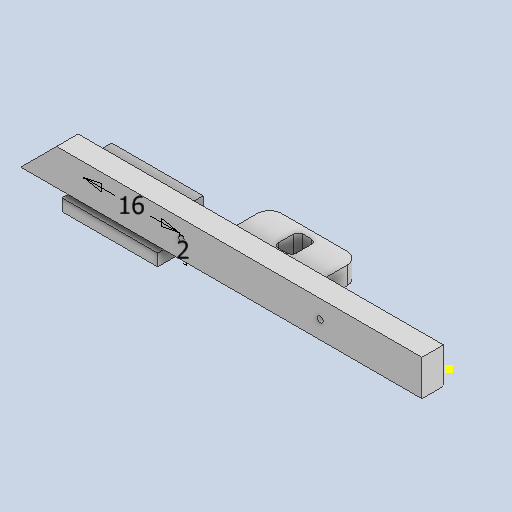
# Autodesk Inventor part: micro_switch_cap
Saved by Autodesk Inventor 2025 (Build 290162000, 162)
## iProperties
Created: 2026-11-09
Part Number: micro_switch_cap
Material: Типовые
Document SubType Name: Modeling
Designer: garin
Density: 1 g/cm^3
Appearance: По умолчанию
Author: garin
Autodesk Inventor part; units mm, degrees
ref_plane "YZ Plane" through (0, 0, 0) normal (1, 0, 0) x (0, 1, 0)
ref_plane "XZ Plane" through (0, 0, 0) normal (0, 1, 0) x (-1, 0, 0)
ref_plane "XY Plane" through (0, 0, 0) normal (0, 0, 1) x (1, 0, 0)
sketch "Эскиз1" plane through (0, 0, 0) normal (0, 0, 1) x (1, 0, 0)
  line L0 (0, 0) -> (-1, 0) construction
  line L1 (-68.1, 3) -> (-1, 3)
  line L2 (-1, 3) -> (-1, -3)
  line L3 (-1, -3) -> (-68.1, -3)
  line L4 (-68.1, -3) -> (-68.1, 3)
  line L5 (-68.1, -3) -> (-62.1, 3)
  line L6 (-68.1, -3) -> (-59.6147, -3) construction
  dimension "d0" = 1
  dimension "d1" = 6
  dimension "d2" = 67.1
  dimension "d3" = 45
  constraints: 14 end point, 3 horizontal, 2 parallel, 1 equal length, 1 midpoint, 1 perpendicular, 1 point on line
  measures "d0" distance of L0.end L0.start
  measures "d1" distance of L1.end L2.end
  measures "d2" distance of L2.end L3.end
  measures "d3" angle of L6 L5
extrude "Выдавливание1" add sketch "Эскиз1" along normal blind 3.6 contours L1 L2 L3 L5
sketch "Эскиз2" plane through (0, 0, 0) normal (0, 0, -1) x (-1, 0, 0)
  line L0 (44.7, 1) -> (60.7, 1) projected
  line L1 (60.7, 1) -> (61.7, 0) projected
  line L2 (61.7, 0) -> (61.7, -3.5) projected
  line L3 (44.7, 1) -> (44.7, -4) projected
  line L4 (44.7, -4) -> (44.7, -6)
  line L5 (44.7, -6) -> (61.7, -6)
  line L6 (61.7, -6) -> (61.7, -3.5)
  line L7 (60.4929, 0.5) -> (45.2, 0.5)
  line L8 (45.2, 0.5) -> (45.2, -4)
  line L9 (45.2, -4) -> (45.2, -5.5)
  line L10 (45.2, -5.5) -> (61.2, -5.5)
  line L11 (61.2, -5.5) -> (61.2, -3.5)
  line L12 (61.2, -3.5) -> (61.2, -0.2071)
  line L13 (61.2, -0.2071) -> (60.4929, 0.5)
  line L14 (61.2, -5.5) -> (61.2, -6)
  line L15 (45.2, -5.5) -> (45.2, -6)
  point P0 (0, 0)
  dimension "d6" = 2
  dimension "d7" = 0.5
  constraints: 24 end point, 6 perpendicular, 2 point on line, 1 vertical, 6 other
  measures "d6" distance of L3.end L4.end
  measures "d7" distance between parallel lines of L0 L7
extrude "Выдавливание2" add sketch "Эскиз2" along normal blind 4 contours L15 L10 L14 L5 | L9 L8 L7 L13 L12 L11 L10
sketch "Эскиз3" plane through (0, 0, 0) normal (0, 0, 1) x (1, 0, 0)
  line L0 (-61.2, -6) -> (-61.2, -3) projected
  line L1 (-68.1, -3) -> (-1, -3) projected
  line L2 (-61.2, -6) -> (-45.2, -6)
  line L3 (-45.2, -6) -> (-45.2, -3)
  line L4 (-45.2, -3) -> (-61.2, -3)
  line L5 (-61.2, -3) -> (-61.2, -6)
  line L6 (-61.2, -6) -> (-45.2, -6)
  line L7 (-45.2, -6) -> (-45.2, -4)
  line L8 (-45.2, -4) -> (-61.2, -4)
  line L9 (-61.2, -4) -> (-61.2, -6)
  point P0 (0, 0)
  dimension "d10" = 16
  dimension "d11" = 2
  constraints: 16 end point, 4 parallel, 2 horizontal, 2 perpendicular, 2 point on line
  measures "d10" distance of L4.end L3.end
  measures "d11" distance of L7.end L6.end
extrude "Выдавливание3" add sketch "Эскиз3" along normal blind 3.6
extrude "Выдавливание4" cut sketch "Эскиз3" against normal blind 1 from surface at 3.6 contours L0 L1 L3 L8
sketch "Эскиз4" plane through (0, 0, 0) normal (0, 0, -1) x (-1, 0, 0)
  circle A0 centre (41.2, 0) radius 0.5 projected
  circle A1 centre (41.2, 0) radius 2.5 projected
  line L0 (37.6, 1.5) -> (21.6, 1.5) projected
  line L1 (37.6, -1.5) -> (37.6, 1.5) projected
  line L2 (21.6, -1.5) -> (37.6, -1.5) projected
  line L3 (21.6, 1.5) -> (21.6, -1.5) projected
  circle A2 centre (18, 0) radius 0.5 projected
  circle A3 centre (18, 0) radius 2.5 projected
  line L4 (21.75, 1.35) -> (37.45, 1.35)
  line L5 (37.45, 1.35) -> (37.45, -1.35)
  line L6 (37.45, -1.35) -> (21.75, -1.35)
  line L7 (21.75, -1.35) -> (21.75, 1.35)
  point P0 (0, 0)
  dimension "d16" = 0.15
  constraints: 8 end point, 3 other
  measures "d16" distance between parallel lines of L0 L4
extrude "Выдавливание5" cut sketch "Эскиз4" against normal blind 2 contours A0 | A1 | A2 | A3
sketch "Эскиз5" plane through (0, 0, 0) normal (0, 0, -1) x (-1, 0, 0)
  circle A0 centre (41.2, 0) radius 0.5 projected
  circle A1 centre (18, 0) radius 0.5 projected
  line L0 (-44.7, 1) -> (-60.7, 1) projected
  line L1 (-61.7, 0) -> (-60.7, 1) projected
  line L2 (-61.7, -3.5) -> (-61.7, 0) projected
  line L3 (-61.7, -3.5) -> (-68.2, -3.5) projected
  line L4 (-68.2, -3) -> (-68.2, -3.5) projected
  line L5 (-61.2, 4) -> (-68.2, -3) projected
  line L6 (-61.2, 4) -> (61.2, 4) projected
  line L7 (68.2, -3) -> (61.2, 4) projected
  line L8 (68.2, -3.5) -> (68.2, -3) projected
  line L9 (68.2, -3.5) -> (61.7, -3.5) projected
  line L10 (61.7, 0) -> (61.7, -3.5) projected
  line L11 (60.7, 1) -> (61.7, 0) projected
  line L12 (44.7, 1) -> (60.7, 1) projected
  line L13 (44.7, 1) -> (44.7, -4) projected
  line L14 (44.7, -4) -> (-44.7, -4) projected
  line L15 (-44.7, -4) -> (-44.7, 1) projected
  circle A2 centre (41.2, 0) radius 2.5 projected
  circle A3 centre (18, 0) radius 2.5 projected
  line L16 (21.6, 1.5) -> (21.6, -1.5) projected
  line L17 (21.6, -1.5) -> (37.6, -1.5) projected
  line L18 (37.6, -1.5) -> (37.6, 1.5) projected
  line L19 (37.6, 1.5) -> (21.6, 1.5) projected
  circle A4 centre (-41.2, 0) radius 2.5 projected
  circle A5 centre (-18, 0) radius 2.5 projected
  line L20 (-21.6, -1.5) -> (-21.6, 1.5) projected
  line L21 (-21.6, 1.5) -> (-37.6, 1.5) projected
  line L22 (-37.6, 1.5) -> (-37.6, -1.5) projected
  line L23 (-37.6, -1.5) -> (-21.6, -1.5) projected
  point P0 (0, 0)
extrude "Выдавливание6" cut sketch "Эскиз5" against normal blind 3.6 contours A0 | A1
sketch "Эскиз6" plane through (0, 0, 0) normal (0, 0, -1) x (-1, 0, 0)
  line L0 (-44.7, 1) -> (-60.7, 1) projected
  line L1 (-61.7, 0) -> (-60.7, 1) projected
  line L2 (-61.7, -3.5) -> (-61.7, 0) projected
  line L3 (-61.7, -3.5) -> (-68.2, -3.5) projected
  line L4 (-68.2, -3) -> (-68.2, -3.5) projected
  line L5 (-61.2, 4) -> (-68.2, -3) projected
  line L6 (-61.2, 4) -> (61.2, 4) projected
  line L7 (68.2, -3) -> (61.2, 4) projected
  line L8 (68.2, -3.5) -> (68.2, -3) projected
  line L9 (68.2, -3.5) -> (61.7, -3.5) projected
  line L10 (61.7, 0) -> (61.7, -3.5) projected
  line L11 (60.7, 1) -> (61.7, 0) projected
  line L12 (44.7, 1) -> (60.7, 1) projected
  line L13 (44.7, 1) -> (44.7, -4) projected
  line L14 (44.7, -4) -> (-44.7, -4) projected
  line L15 (-44.7, -4) -> (-44.7, 1) projected
  circle A0 centre (41.2, 0) radius 2.5 projected
  circle A1 centre (18, 0) radius 2.5 projected
  line L16 (21.6, 1.5) -> (21.6, -1.5) projected
  line L17 (21.6, -1.5) -> (37.6, -1.5) projected
  line L18 (37.6, -1.5) -> (37.6, 1.5) projected
  line L19 (37.6, 1.5) -> (21.6, 1.5) projected
  circle A2 centre (-41.2, 0) radius 2.5 projected
  circle A3 centre (-18, 0) radius 2.5 projected
  line L20 (-21.6, -1.5) -> (-21.6, 1.5) projected
  line L21 (-21.6, 1.5) -> (-37.6, 1.5) projected
  line L22 (-37.6, 1.5) -> (-37.6, -1.5) projected
  line L23 (-37.6, -1.5) -> (-21.6, -1.5) projected
  line L24 (37.6, -1.5) -> (37.1, -1.5)
  line L25 (37.1, -1.5) -> (37.1, 1.5)
  line L26 (37.1, 1.5) -> (37.6, 1.5)
  line L27 (37.6, 1.5) -> (37.6, -1.5)
  line L28 (29.6, -1.5) -> (29.6, 1.5) construction
  line L29 (22.1, -1.5) -> (22.1, 1.5)
  point P0 (0, 0)
  point P1 (22.1, 1.5)
  dimension "d30" = 0.5
  constraints: 12 end point, 2 midpoint, 2 parallel, 2 symmetric about line, 1 horizontal, 1 perpendicular, 1 point on line
  measures "d30" distance of L25.end L26.end
extrude "Выдавливание7" add sketch "Эскиз6" along normal blind 7 contours L19 L25 L17 L29
sketch "Эскиз7" plane through (-37.6, -1.5, 0) normal (0, -1, 0) x (1, 0, 0)
  line L0 (15.5, -7) -> (0.5, -7) construction
  line L1 (8, -7) -> (8, -5.8) construction
  line L2 (6.5, -5.8) -> (9.5, -5.8)
  line L3 (9.5, -5.8) -> (9.5, -1.7)
  line L4 (9.5, -1.7) -> (6.5, -1.7)
  line L5 (6.5, -1.7) -> (6.5, -5.8)
  point P0 (37.6, 0)
  point P1 (16, -7)
  point P2 (0, -7)
  dimension "d23" = 1.2
  dimension "d24" = 3
  dimension "d25" = 4.1
  constraints: 10 end point, 2 midpoint, 2 parallel, 1 horizontal, 1 perpendicular, 1 vertical
  measures "d23" distance of L1.end L1.start
  measures "d24" distance of L4.end L3.end
  measures "d25" distance of L3.end L2.end
extrude "Выдавливание8" cut sketch "Эскиз7" against normal blind 7
fillet "Сопряжение1" radius 0.8 4 edges at (-28.1, 0, -1.7) (-31.1, 0, -1.7) (-28.1, 0, -5.8) (-31.1, 0, -5.8)
fillet "Сопряжение2" radius 2 2 edges at (-22.1, 0, -7) (-37.1, 0, -7)
